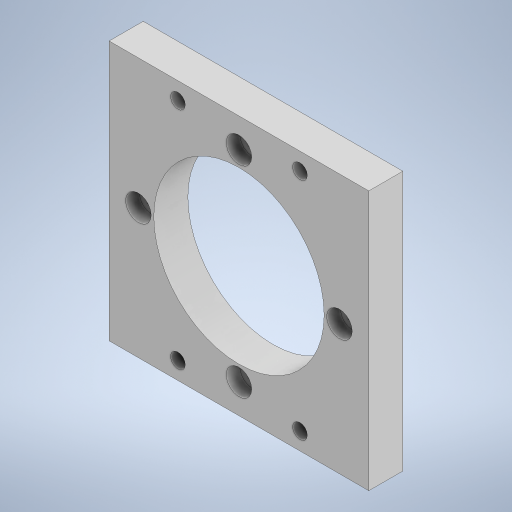
# Autodesk Inventor part: PRS-110-Adaptertop_V2
Saved by Autodesk Inventor 2023 (Build 270158000, 158)
## iProperties
Created: 2023-07-07
Part Number: PRS-110-Adaptertop_V2
Material: Generic
Document SubType Name: Modeling
Designer: B0067-WS-2
Density: 1 g/cm^3
Appearance: Default
Author: B0067-WS-2
Autodesk Inventor part; units mm, degrees
ref_plane "YZ Plane" through (0, 0, 0) normal (1, 0, 0) x (0, 1, 0)
ref_plane "XZ Plane" through (0, 0, 0) normal (0, 1, 0) x (-1, 0, 0)
ref_plane "XY Plane" through (0, 0, 0) normal (0, 0, 1) x (1, 0, 0)
sketch "Sketch2" plane through (0, 0, 0) normal (0, 0, 1) x (1, 0, 0)
  line L0 (-53.34, 0) -> (53.34, 0) construction
  line L1 (0, -53.34) -> (0, 53.34) construction
  line L2 (-38.1, 38.1) -> (38.1, 38.1)
  line L3 (38.1, 38.1) -> (38.1, -38.1)
  line L4 (38.1, -38.1) -> (-38.1, -38.1)
  line L5 (-38.1, -38.1) -> (-38.1, 38.1)
  circle A0 centre (0, 0) radius 25
  dimension "d1" = 76.2
  dimension "d2" = 76.2
  dimension "d0" = 50
  constraints: 12 end point, 2 parallel, 1 centre point, 1 coincident, 1 horizontal, 1 perpendicular, 2 other
  measures "d1" distance between parallel lines of L4 L2
  measures "d2" distance of L2.start L2.end
  measures "d0" diameter of A0
extrude "Extrusion1" add sketch "Sketch2" along normal blind 10
sketch "Sketch3" plane through (0, 0, 10) normal (0, 0, 1) x (1, 0, 0)
  circle A0 centre (0, 0) radius 29.5 construction
  point P0 (0, 29.5)
  point P1 (-29.5, 0)
  point P2 (0, -29.5)
  point P3 (29.5, 0)
  dimension "d6" = 59
  constraints: 4 point on circle, 1 centre point, 1 coincident
  measures "d6" diameter of A0
hole "Hole1" at (0, 29.5, 10) at (-29.5, 0, 10) at (0, -29.5, 10) at (29.5, 0, 10) direction (0, 0, -1) diameter 4.1 end through all counterbore diameter 7.5 counterbore depth 4
sketch "Sketch4" plane through (0, 0, 0) normal (0, 0, -1) x (-1, 0, 0)
  circle A0 centre (0, -29.5) radius 2.05 construction
  circle A1 centre (0, 29.5) radius 2.05 construction
  circle A2 centre (29.5, 0) radius 2.05 construction
  circle A3 centre (-29.5, 0) radius 2.05 construction
  line L0 (38.1, -38.1) -> (-38.1, -38.1) construction
  line L1 (38.1, 38.1) -> (38.1, -38.1) construction
  line L2 (-38.1, 38.1) -> (38.1, 38.1) construction
  line L3 (-38.1, -38.1) -> (-38.1, 38.1) construction
  circle A4 centre (0, 0) radius 25 construction
  line L4 (53.34, 0) -> (-53.34, 0) construction
  line L5 (0, -53.34) -> (0, 53.34) construction
  line L6 (17.9085, -33.02) -> (-17.9085, -33.02) construction
  line L7 (-17.9085, -33.02) -> (-17.9085, 33.02) construction
  line L8 (-17.9085, 33.02) -> (17.9085, 33.02) construction
  line L9 (17.9085, 33.02) -> (17.9085, -33.02) construction
  dimension "d14" = 17.9085
  dimension "d15" = 33.02
  constraints: 8 end point, 4 coincident, 2 parallel, 1 horizontal, 1 perpendicular, 2 other
  measures "d14" distance between parallel lines of L5 L7
  measures "d15" distance between parallel lines of L4 L6
hole "Hole2" at (-17.9085, -33.02, 0) at (17.9085, -33.02, 0) at (17.9085, 33.02, 0) at (-17.9085, 33.02, 0) direction (0, 0, 1) diameter 4.318 end through all counterbore diameter 7.2 counterbore depth 4.4
body "Solid1"
